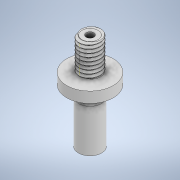
# Autodesk Inventor part: filet_surub
Saved by Autodesk Inventor 2022.6 (Build 266554000, 554)
## iProperties
Created: 2026-07-30
Part Number: filet_surub
Material: Generic
Document SubType Name: Modeling
Designer: Dragos Macovei
Density: 1 g/cm^3
Appearance: Default
Author: Dragos Macovei
Autodesk Inventor part; units mm, degrees
ref_plane "YZ Plane" through (0, 0, 0) normal (1, 0, 0) x (0, 1, 0)
ref_plane "XZ Plane" through (0, 0, 0) normal (0, 1, 0) x (-1, 0, 0)
ref_plane "XY Plane" through (0, 0, 0) normal (0, 0, 1) x (1, 0, 0)
sketch "Sketch1" plane through (0, 0, 0) normal (0, 1, 0) x (-1, 0, 0)
  circle A0 centre (0, 0) radius 3
  dimension "d0" = 6
  constraints: 1 centre point, 1 coincident
  measures "d0" diameter of A0
extrude "Extrusion1" add sketch "Sketch1" along normal blind 9
sketch "Sketch2" plane through (0, 0, 0) normal (1, 0, 0) x (0, 1, 0)
  point P0 (0, 0)
thread "Thread1" size "M6x1" class "6g" standard "ANSI Metric M Profile" full length
sketch "Sketch4" plane through (0, 9, 0) normal (1, 0, 0) x (0, 0, 1)
  line L0 (3, 0) -> (3, 9)
  line L1 (3, 9) -> (2.2585, 9)
  line L2 (2.2585, 9) -> (2.2585, 0)
  line L3 (2.2585, 0) -> (3, 0)
  line L4 (0, -3.1086) -> (0, 11.0181) projected
  constraints: 8 end point
revolve "Revolution1" cut sketch "Sketch4" angle 360 about axis through (0, 9, 0) along (0, -1, 0)
sketch "Sketch5" plane through (0, 9, 0) normal (1, 0, 0) x (0, 0, 1)
  line L0 (3, 0) -> (3, 9)
  line L1 (3, 9) -> (2.2585, 9)
  line L2 (2.2585, 9) -> (2.2585, 0)
  line L3 (2.2585, 0) -> (3, 0)
  line L4 (0, -3.1086) -> (0, 11.0181) projected
  constraints: 8 end point
revolve "Revolution2" add sketch "Sketch5" angle 360 about axis through (0, 9, 0) along (0, -1, 0) separate body
sketch "Sketch3" plane through (0, 9, 0) normal (-1, 0, 0) x (0, -1, 0)
  line L0 (-0.5834, -2.3093) -> (-0.5001, -2.3093) construction
  line L1 (0.0832, -2.9496) -> (-0.0001, -3.1097) construction
  line L2 (-1.0001, -3.1097) -> (-1.0834, -2.9496) construction
  line L3 (-0.4168, -2.3093) -> (-0.5001, -2.1492) construction
  line L4 (-0.5001, -2.1492) -> (-0.5834, -2.3093) construction
  line L5 (-1.0001, -3.1097) -> (-0.9168, -2.9496) construction
  line L6 (-0.4168, -2.3093) -> (-0.0834, -2.9496)
  line L7 (-1.0834, -2.9496) -> (-0.9168, -2.9496) construction
  arc A0 (-1.0834, -2.9496) -> (-1.0001, -3.0002) centre (-1.0001, -2.9062) ccw construction
  line L8 (0.0832, -2.9496) -> (-0.0834, -2.9496) construction
  line L9 (-1.0001, -3.1097) -> (-1.0001, -2.9496) construction
  line L10 (-0.0001, -3.1097) -> (-0.0001, -2.9496) construction
  line L11 (-0.5001, -2.1492) -> (-0.5001, -2.2587) construction
  line L12 (-1.0001, -3.0002) -> (-0.0001, -3.0002)
  arc A1 (-1.0001, -3.0002) -> (-0.9168, -2.9496) centre (-1.0001, -2.9062) ccw
  line L13 (-0.0834, -2.9496) -> (-0.0001, -3.1097) construction
  line L14 (-0.9168, -2.9496) -> (-0.5834, -2.3093)
  line L15 (-0.0001, -0.0002) -> (-0.0001, 0.0177)
  line L16 (-0.0001, 0.0177) -> (-0.0001, -0.0002)
  line L17 (-0.0001, -0.0002) -> (0.0334, -0.0002)
  arc A2 (-0.0834, -2.9496) -> (-0.0001, -3.0002) centre (-0.0001, -2.9062) ccw
  arc A3 (-0.0001, -3.0002) -> (0.0832, -2.9496) centre (-0.0001, -2.9062) ccw construction
  arc A4 (-0.5001, -2.2587) -> (-0.5834, -2.3093) centre (-0.5001, -2.3527) ccw
  arc A5 (-0.4168, -2.3093) -> (-0.5001, -2.2587) centre (-0.5001, -2.3527) ccw
  line L18 (-0.5001, -2.2587) -> (-0.5001, -2.3093) construction
  line L19 (-0.5001, -2.3093) -> (-0.4168, -2.3093) construction
  dimension "d5" = 55
  dimension "d6" = 0.1601
  dimension "d7" = 0.1601
  dimension "Sketch3_ThreadOffset" = 0
  dimension "Sketch3_MajorRadius" = 3
  dimension "d10" = 1
  dimension "Sketch3_MinorRadius" = 2.2585
  constraints: 40 end point, 12 point on circle, 10 parallel, 8 tangent, 6 centre point, 6 collinear, 2 midpoint, 2 point on line, 1 horizontal, 1 perpendicular, 3 other
  measures "d5" angle of L6 L14
  measures "d6" distance of L3.end L0.end
  measures "d7" distance of L1.end L10.end
  measures "Sketch3_ThreadOffset" distance between parallel lines of L15 L10
  measures "Sketch3_MajorRadius" distance from line of L12 L15.start
  measures "d10" distance from line of L1.end L9
  measures "Sketch3_MinorRadius" distance edge to line of A5 L17
coil "Coil1" sketch "Sketch3" operation cut axis through (0, 9, 0) along (0, -1, 0) pitch 1.001 turns 10.989011 hand right bodies 2
sketch "Sketch6" plane through (0, 0, 0) normal (1, 0, 0) x (0, 1, 0)
  line L0 (0.9855, -3) -> (9, -3) construction
  line L1 (7.9633, -3) -> (3.3659, -3) construction
  line L2 (0.485, 3) -> (8.5052, 3) construction
  line L3 (7.4707, 3) -> (3.3659, 3) construction
  point P0 (0, 0)
  constraints: 4 end point, 4 point on line
sketch "Sketch7" plane through (0, 9, 0) normal (0, 1, 0) x (1, 0, 0)
  circle A0 centre (0, 0) radius 1.1
  dimension "d24" = 2.2
  constraints: 1 centre point, 1 coincident
  measures "d24" diameter of A0
sketch "Sketch8" plane through (0, 0, 0) normal (0, -1, 0) x (1, 0, 0)
  circle A0 centre (0, 0) radius 6.5
  dimension "d25" = 13
  constraints: 1 centre point, 1 coincident
  measures "d25" diameter of A0
extrude "Extrusion2" add sketch "Sketch8" along normal blind 3 bodies 1
sketch "Sketch9" plane through (0, -3, 0) normal (0, -1, 0) x (1, 0, 0)
  circle A0 centre (0, 0) radius 3.25
  dimension "d28" = 6.5
  constraints: 1 centre point, 1 coincident
  measures "d28" diameter of A0
extrude "Extrusion3" add sketch "Sketch9" along normal blind 15 bodies 1
fillet "Fillet1" radius 3 1 edges at (-3.25, -3, 0)
extrude "Extrusion4" cut sketch "Sketch7" against normal through all bodies 1
equation "\"d5\" = d12"
equation "\"d6\" = 0.160083 * Sketch3_Pitch"
equation "\"d7\" = 0.160083 * Sketch3_Pitch"
equation "\"d10\" = Sketch3_Pitch"
equation "\"d12\" = 55deg"
equation "\"Sketch3_Pitch\" = 1"
body "Solid1"
body "Solid2"
